Autodesk Fusion 360 part; units mm, degrees
(part 2 of 2)
equation "n_base_bolt = 4" comment "SKELETON P04 DECIDED: PM ruling 2026-10-31, J-BASE-01: bolts per panel along the band, evenly spaced"
equation "base_spigot_inset = spigot_inset" comment "SKELETON P04 DECIDED: J-BASE-01: the spigot rule (kept by this name for parts already linked)"
equation "base_side_y0 = pod_d / 2 - wall_depth + seam_gap" comment "SKELETON P04 CALCULATION: J-BASE-01: side bolt lines start at the side panel's front end (first bolt base_bolt_edge further on)"
equation "side_base_pitch = ( side_l - 2 * base_bolt_edge ) / ( n_base_bolt - 1 )" comment "SKELETON P04 CALCULATION: J-BASE-01 bolt pitch along a side panel"
equation "base_back_x0 = pod_w / 2 - outer_t - seam_gap" comment "SKELETON P04 CALCULATION: J-BASE-01: back bolt lines start at each back FRAME's outer end, X -/+ this (first bolt base_bolt_edge further in)"
equation "back_base_pitch = ( half_fw - 2 * base_bolt_edge ) / ( n_base_bolt - 1 )" comment "SKELETON P04 DECIDED: PM ruling 2026-10-31 (Reviewer 5 P2 on #58): J-BASE-01 pitch along a back panel, measured on the FRAME (half_fw), where the bolts go; 'panel end' means the frame end"
equation "ceil_bolt_z = pod_h - outer_t + frame_t / 2" comment "SKELETON P04 DECIDED: PM ruling 2026-10-31, J-CEIL-01 wall to ceiling: the bolt line on the ceiling frame's centre (Z 2374)"
equation "n_ceil_side_bolt = 4" comment "SKELETON P04 DECIDED: PM ruling 2026-10-31, J-CEIL-01: bolts along each side wall top"
equation "n_ceil_back_bolt = 4" comment "SKELETON P04 DECIDED: PM ruling 2026-10-31, J-CEIL-01: bolts along each back panel top, like the base (pitch about 253, every edge 350 or less; joints register: 82 bolts in all)"
equation "ceil_side_y0 = pod_d / 2 - wall_depth" comment "SKELETON P04 DECIDED: PM ruling 2026-10-31 (joints register): J-CEIL-01 side bolt lines start at Y -645, measured along the ceiling (first bolt bolt_edge_inset further on)"
equation "ceil_side_pitch = ( wall_depth - 2 * bolt_edge_inset ) / ( n_ceil_side_bolt - 1 )" comment "SKELETON P04 DECIDED: PM ruling 2026-10-31 (joints register): J-CEIL-01 pitch along a side wall top, over the ceiling's length (was over the side panel's)"
equation "ceil_back_x0 = pod_w / 2 - outer_t - seam_gap" comment "SKELETON P04 DECIDED: PM ruling 2026-10-31 (joints register): J-CEIL-01 back bolt lines start at each back frame's outer end, X -/+ this"
equation "ceil_back_pitch = ( half_fw - 2 * bolt_edge_inset ) / ( n_ceil_back_bolt - 1 )" comment "SKELETON P04 DECIDED: PM ruling 2026-10-31 (joints register): J-CEIL-01 pitch along a back panel top, on the frame (half_fw)"
equation "sk_ref = 5000 mm" comment "ASSUMPTION: sketch reference point offset: every sketch corner is dimensioned from a point at -sk_ref on both plane axes, so no dimension changes side when a corner crosses a pod centre line in an edit"
equation "fg_vis_zb = wall_z0" comment "CALCULATION: visible bottom of the fixed pane = the base band top (DL and DR stop there too, PM ruling 2026-10-31)"
equation "fg_vis_zt = dt_zb" comment "CALCULATION: visible top of the fixed pane = DT's underside"
equation "fg_gap = glass_gap" comment "CALCULATION: = the skeleton's glass_gap: the pane's free edge runs parallel to the door's latch edge, 4 mm off (PM ruling 2026-10-31; the skeleton's fix_xbl and fix_xtl follow the same rule since its update #58)"
equation "gu_prof_w = 15 mm" comment "SOURCE: Bohle BO5201571 aluminium U-profile 15 x 15 x 1.5 (hardware selection C5)"
equation "gu_prof_d = 15 mm" comment "SOURCE: as gu_prof_w"
equation "gu_prof_t = 1.5 mm" comment "SOURCE: as gu_prof_w"
equation "gu_w = gu_prof_w - 2 * gu_prof_t" comment "CALCULATION: inner width of the U-profile = the U-seal's outer width"
equation "gu_base = 2 mm" comment "ASSUMPTION: U-seal base under the glass edge; HOLD for Bohle's BO5201735 section drawing"
equation "gu_in_d = gu_prof_d - gu_prof_t" comment "CALCULATION: inner depth of the U-profile"
equation "fg_bite = gu_in_d - gu_base" comment "CALCULATION: glass cover in the hidden channels, 11.5 (PM ruling 2026-10-31); HOLD for the glass supplier's minimum"
equation "fg_r_len = sqrt(( fix_xbr - fix_xk ) * ( fix_xbr - fix_xk ) + ( fix_zk - fix_zb ) * ( fix_zk - fix_zb ))" comment "CALCULATION: length of the skeleton's right edge (bottom-right corner to the knee)"
equation "fg_rnx = ( fix_zk - fix_zb ) / fg_r_len" comment "CALCULATION: right edge outward normal, X"
equation "fg_rnz = ( fix_xk - fix_xbr ) / fg_r_len" comment "CALCULATION: right edge outward normal, Z"
equation "fg_rc = fg_rnx * ( pod_w / 2 - fix_xbr ) + fg_rnz * fix_zb" comment "CALCULATION: right edge line constant"
equation "fg_d_len = sqrt(( pod_w - fix_xtr - fix_xk ) * ( pod_w - fix_xtr - fix_xk ) + ( dt_zb - fix_zk ) * ( dt_zb - fix_zk ))" comment "CALCULATION: length of DR's diagonal inner edge (knee to DT's underside at X -pod_w/2 + fix_xtr)"
equation "fg_dnx = ( dt_zb - fix_zk ) / fg_d_len" comment "CALCULATION: diagonal outward normal, X"
equation "fg_dnz = ( pod_w - fix_xtr - fix_xk ) / fg_d_len" comment "CALCULATION: diagonal outward normal, Z"
equation "fg_dc = fg_dnx * ( pod_w / 2 - fix_xk ) + fg_dnz * fix_zk" comment "CALCULATION: diagonal line constant"
equation "fg_det = fg_rnx * fg_dnz - fg_rnz * fg_dnx" comment "CALCULATION: for the knee corner"
equation "fg_l_len = sqrt(( door_xbr - door_xtr ) * ( door_xbr - door_xtr ) + ( door_zt - door_zb ) * ( door_zt - door_zb ))" comment "CALCULATION: length of the door's latch edge"
equation "fg_lnx = ( door_zt - door_zb ) / fg_l_len" comment "CALCULATION: door latch edge normal toward the pane, X"
equation "fg_lnz = ( door_xbr - door_xtr ) / fg_l_len" comment "CALCULATION: door latch edge normal toward the pane, Z"
equation "fg_lc = fg_lnx * ( -pod_w / 2 + door_xbr ) + fg_lnz * door_zb" comment "CALCULATION: door latch edge line constant"
equation "dt_skin_t = 3 mm" comment "SOURCE: ACP 3 mm, EV3038 Dark Yellow (D-12; hardware selection A1)"
equation "dt_fo = dt_skin_t + bond_t" comment "CALCULATION: a frame tube's face from the skin's outer face: the 3 mm ACP and the 3 mm bond line (skeleton bond_t; the bond spec's joint, at least 12 wide x 3 thick, D-137), so every tube that bonds to the skin stands 3 mm off it (PM ruling 2026-11-01)"
equation "dt_back_t = 2 mm" comment "CONFIRMED: back plate 2 mm aluminium: J-FRONT-03 puts the ceiling bolts' rivnuts in it, 1.0 to 2.7 thick at each bolt (HOLD-10: 2 mm; PM ruling 2026-11-01)"
equation "dt_stop_gap = 2.26 mm" comment "SOURCE: J-FRONT-03: DT's back plate stands 2.26 in front of the ceiling's front face (Y -645), the stopped seam's gap (rivnut head 0.76 on a 1.5 stop washer, R-J5)"
equation "jf3_x0 = -1201.74 mm" comment "SOURCE: joints register 2.9: DT's bolt line starts at C1's frame end, X -1201.74"
equation "jf3_e = 220 mm" comment "SOURCE: R-J13: the end bolts 220 in from each end of the edge"
equation "jf3_z = 2374 mm" comment "SOURCE: R-J15: the bolt line on the ceiling's front tube centre, Z 2374"
equation "jf3_hole = 9.53 mm" comment "SOURCE: rivnut 838003 hole 9.53 +0.10/0 (joints register H-03)"
equation "jf3_tail = 14 mm" comment "CALCULATION: holes in the top back tube's back wall round the rivnut tails and the bolt tips, as J-FRONT-01's"
equation "fr_wtop = 40 mm" comment "CONFIRMED: the back ring's top tube 40 x 20, so the J-FRONT-03 rivnut tails at Z 2374 go into it (PM ruling 2026-11-01)"
equation "sp_x1 = -pod_w / 2 + dt_xr - 179 mm" comment "CONFIRMED: the round spigot hole, X 270: 36 in from the left end of DR's ledge tube (X 234 to 449)"
equation "sp_dx = 140 mm" comment "CONFIRMED: the slot 140 from the round hole (PM ruling 2026-11-01)"
equation "sp_y = -pod_d / 2 + decor_d - 12.88 mm" comment "CALCULATION: the spigots' Y, -657.88: the middle of where DR's ledge tube (Y -666.5 to -646.5) and DT's bottom back tube overlap"
equation "sp_hole = 8.5 mm" comment "SOURCE: R-J13: spigot hole 8.5 round at one end, 8.5 x 14 slot at the other"
equation "sp_slot = 14 mm" comment "SOURCE: R-J13: the slot 14 long along the edge"
equation "sp_skin = 16 mm" comment "CALCULATION: the underside's notch over DR's ledge reaches this far past each spigot, clear of the rivnut heads (12.96)"
equation "stop_fl = 20 mm" comment "SOURCE: the top stop's flange under DT's underside (the 20 x 20 x 2 angle), screwed up into the rail F02"
equation "stop_hole = 4.3 mm" comment "SOURCE: ISO 273 fine clearance for M4 countersunk screws through the flange, 2.1 diameters from its free edge (screw and rivnut: joints register numbers HOLD)"
equation "dt_m = ( dl_zo - dt_zb ) / dl_w" comment "CALCULATION: rise of the slope DT shares with DL, per unit of X"
equation "dt_k = sqrt(1 + dt_m * dt_m)" comment "CALCULATION: for pushing the slope line in by the skin"
equation "slot_clear = 1 mm" comment "ASSUMPTION: fitting clearance each side of the glass channel in the skin slot"
equation "door_top_cut = 2 mm" comment "DECIDED: PM ruling 2026-10-31: 6 mm gap from the leaf to DT for the catch"
equation "leaf_zt = door_zt - door_top_cut" comment "CALCULATION: top of the door leaf"
equation "st_l = 62 mm" comment "SOURCE: Sugatsune HT-MSG62 strike plate, 62 long (datasheet D2, Dec 2020)"
equation "st_a = 14.1 mm" comment "SOURCE: strike HT-MSG62-U10, A = 14.1"
equation "st_end = 25 mm" comment "ASSUMPTION: as the door unit: the strike's end in from the leaf's top latch corner"
equation "ca_l = 62 mm" comment "SOURCE: Sugatsune HT-MSG62 catch, 62 long (datasheet)"
equation "ca_d = 20 mm" comment "SOURCE: catch body depth 20 (datasheet)"
equation "ca_h = 26 mm" comment "SOURCE: catch body with its bracket, 26 below the frame (datasheet)"
equation "stop_gap = 4 mm" comment "SOURCE: athmer PS 1515 P Flex works in a 2 to 6 mm frame gap (selection C3): 4 nominal"
equation "ps_s = 15 mm" comment "SOURCE: athmer PS 1515 P Flex, 15 x 15 (selection C3)"
equation "stop_t = 2 mm" comment "ASSUMPTION: top stop: an aluminium angle leg 2 thick"
equation "stop_h = 20 mm" comment "SOURCE: top stop: a standard 20 x 20 x 2 aluminium angle (EN 755-9); its leg hangs 20 below DT's underside, past the seal"
equation "stop_end = 10 mm" comment "ASSUMPTION: the seal and stop stop 10 short of the catch"
equation "fr_w = 20 mm" comment "CALCULATION: frame tube 20 x 20 x 1.5, 6063-T6 (D-79): bending stiffness about v1's 16 x 16 x 1 steel box, as DR"
equation "fr_t = 1.5 mm" comment "CALCULATION: frame tube wall, as fr_w"
equation "rail_clear = -pod_d / 2 + decor_d - dt_stop_gap - dt_back_t - 2 * fr_w - ( -glass_y + gu_prof_w / 2 )" comment "CALCULATION: the catch and stop rail sits against the back ring's bottom tube, so it stands 2.24 behind the fixed glass's top channel (its back face at Y -691.5); J-FRONT-03 moved the back ring 1.26 forward"
equation "dt_fdx = fix_xtr - dt_x2" comment "CALCULATION: lower front facet in plan, along X"
equation "dt_fdy = pod_d / 2 - dt_y2" comment "CALCULATION: lower front facet in plan, along Y"
equation "dt_fl = sqrt(dt_fdx * dt_fdx + dt_fdy * dt_fdy)" comment "CALCULATION: lower front facet length in plan"
equation "dt_fnx = dt_fdy / dt_fl" comment "CALCULATION: lower front facet normal into DT, X"
equation "dt_fny = dt_fdx / dt_fl" comment "CALCULATION: lower front facet normal into DT, Y"
equation "dt_fc = dt_fnx * ( -pod_w / 2 + fix_xtr ) + dt_fny * ( -pod_d / 2 )" comment "CALCULATION: lower front facet constant"
equation "dt_cl = sqrt(( pod_d / 2 - ch_yb ) * ( pod_d / 2 - ch_yb ) + ( pod_h - ch_zlo ) * ( pod_h - ch_zlo ))" comment "CALCULATION: length of the top chamfer in the side view"
equation "dt_cny = -( pod_h - ch_zlo ) / dt_cl" comment "CALCULATION: top chamfer outward normal, Y"
equation "dt_cnz = ( pod_d / 2 - ch_yb ) / dt_cl" comment "CALCULATION: top chamfer outward normal, Z"
equation "dt_cc = dt_cny * ( -pod_d / 2 ) + dt_cnz * ch_zlo" comment "CALCULATION: top chamfer line constant"
equation "dt_jl = sqrt(( dt_xr - fix_xtr ) * ( dt_xr - fix_xtr ) + ( pod_d / 2 - ch_yb ) * ( pod_d / 2 - ch_yb ))" comment "CALCULATION: length of the DT-DR joint line in plan (v1's line to X 449)"
equation "dt_jnx = -( pod_d / 2 - ch_yb ) / dt_jl" comment "CALCULATION: DT-DR joint normal into DT, X"
equation "dt_jny = ( dt_xr - fix_xtr ) / dt_jl" comment "CALCULATION: DT-DR joint normal into DT, Y"
equation "dt_jc = dt_jnx * ( -pod_w / 2 + fix_xtr ) + dt_jny * ( -pod_d / 2 )" comment "CALCULATION: DT-DR joint constant"
equation "d2514 = sk_ref"
equation "d2515 = sk_ref"
equation "d2516 = ( -pod_w / 2 ) + sk_ref"
equation "d2517 = ( -pod_w / 2 + dl_x2 + 4 mm ) + sk_ref"
equation "d2518 = ( -pod_w / 2 + dt_x2 ) + sk_ref"
equation "d2519 = ( -pod_w / 2 + fix_xtr ) + sk_ref"
equation "d2520 = ( -pod_w / 2 + dt_xr ) + sk_ref"
equation "d2521 = ( -dl_y1 ) + sk_ref"
equation "d2522 = ( -dt_y3 ) + sk_ref"
equation "d2523 = ( -dt_y2 ) + sk_ref"
equation "d2524 = ( -pod_d / 2 ) + sk_ref"
equation "d2525 = ( -ch_yb ) + sk_ref"
equation "d2526 = ( ( -pod_d / 2 + decor_d - dt_stop_gap ) ) + sk_ref"
equation "d2527 = ( dt_zb ) * ( 1 )"
equation "d2528 = ( pod_h ) - ( dt_zb )"
equation "d2530 = sk_ref"
equation "d2531 = sk_ref"
equation "d2532 = ( -pod_w / 2 + dl_w ) + sk_ref"
equation "d2533 = ( -pod_w / 2 ) + sk_ref"
equation "d2534 = ( dt_zb ) + sk_ref"
equation "d2535 = ( dl_zo ) + sk_ref"
equation "d2536 = ( -pod_d / 2 ) * ( 1 )"
equation "d2537 = ( -pod_d / 2 + decor_d ) - ( -pod_d / 2 )"
equation "d2539 = sk_ref"
equation "d2540 = sk_ref"
equation "d2541 = ( ch_zlo ) + sk_ref"
equation "d2542 = ( pod_h ) + sk_ref"
equation "d2543 = ( -ch_yb ) + sk_ref"
equation "d2544 = ( -pod_d / 2 ) + sk_ref"
equation "d2545 = ( -pod_w / 2 ) * ( 1 )"
equation "d2546 = ( pod_w / 2 ) - ( -pod_w / 2 )"
equation "d2548 = dt_skin_t"
equation "d2549 = sk_ref"
equation "d2550 = sk_ref"
equation "d2551 = ( ( ( fg_dc + gu_prof_d - fg_dnz * ( fg_vis_zt ) ) / fg_dnx ) ) + sk_ref"
equation "d2552 = ( ( ( fg_lc + fg_gap - fg_lnz * ( fg_vis_zt + dt_skin_t + 1 mm ) ) / fg_lnx ) ) + sk_ref"
equation "d2553 = ( -glass_y - gu_prof_w / 2 - slot_clear ) + sk_ref"
equation "d2554 = ( -glass_y + gu_prof_w / 2 + slot_clear ) + sk_ref"
equation "d2555 = ( fg_vis_zt - 1 mm ) * ( 1 )"
equation "d2556 = ( fg_vis_zt + dt_skin_t + 1 mm ) - ( fg_vis_zt - 1 mm )"
equation "d2558 = sk_ref"
equation "d2559 = sk_ref"
equation "d2560 = ( ( sp_x1 + sp_dx + ( sp_slot - sp_hole ) / 2 + sp_skin ) ) + sk_ref"
equation "d2561 = ( ( sp_x1 - sp_skin ) ) + sk_ref"
equation "d2562 = ( sp_y - sp_skin ) + sk_ref"
equation "d2563 = ( ( -pod_d / 2 + decor_d - dt_stop_gap ) + 1 mm ) + sk_ref"
equation "d2564 = ( fg_vis_zt - 1 mm ) * ( 1 )"
equation "d2565 = ( fg_vis_zt + dt_skin_t + 1 mm ) - ( fg_vis_zt - 1 mm )"
equation "d2567 = sk_ref"
equation "d2568 = sk_ref"
equation "d2569 = ( ( -pod_w / 2 + dl_w + dt_skin_t * ( dt_k - 1 ) / dt_m ) ) + sk_ref"
equation "d2570 = ( -pod_w / 2 + dt_xr ) + sk_ref"
equation "d2571 = ( ( -pod_w / 2 + dl_w - ( pod_h - dt_skin_t - dt_zb - dt_skin_t * dt_k ) / dt_m ) ) + sk_ref"
equation "d2572 = ( dt_zb + dt_skin_t ) + sk_ref"
equation "d2573 = ( pod_h - dt_skin_t ) + sk_ref"
equation "d2574 = ( ( -pod_d / 2 + decor_d - dt_stop_gap ) - dt_back_t ) * ( 1 )"
equation "d2575 = ( ( -pod_d / 2 + decor_d - dt_stop_gap ) ) - ( ( -pod_d / 2 + decor_d - dt_stop_gap ) - dt_back_t )"
equation "d2577 = sk_ref"
equation "d2578 = sk_ref"
equation "d2579 = ( ( jf3_x0 + jf3_e + 0 * ( -pod_w / 2 + dt_xr - jf3_x0 - 2 * jf3_e ) / 3 ) ) + sk_ref"
equation "d2580 = ( jf3_z ) + sk_ref"
equation "d2581 = jf3_hole"
equation "d2582 = ( ( jf3_x0 + jf3_e + 1 * ( -pod_w / 2 + dt_xr - jf3_x0 - 2 * jf3_e ) / 3 ) ) + sk_ref"
equation "d2583 = ( jf3_z ) + sk_ref"
equation "d2584 = jf3_hole"
equation "d2585 = ( ( jf3_x0 + jf3_e + 2 * ( -pod_w / 2 + dt_xr - jf3_x0 - 2 * jf3_e ) / 3 ) ) + sk_ref"
equation "d2586 = ( jf3_z ) + sk_ref"
equation "d2587 = jf3_hole"
equation "d2588 = ( ( jf3_x0 + jf3_e + 3 * ( -pod_w / 2 + dt_xr - jf3_x0 - 2 * jf3_e ) / 3 ) ) + sk_ref"
equation "d2589 = ( jf3_z ) + sk_ref"
equation "d2590 = jf3_hole"
equation "d2591 = ( ( -pod_d / 2 + decor_d - dt_stop_gap ) - dt_back_t - 1 mm ) * ( 1 )"
equation "d2592 = ( ( -pod_d / 2 + decor_d - dt_stop_gap ) + 1 mm ) - ( ( -pod_d / 2 + decor_d - dt_stop_gap ) - dt_back_t - 1 mm )"
equation "d2594 = sk_ref"
equation "d2595 = sk_ref"
equation "d2596 = ( ( ( -pod_w / 2 + door_xbr - ( door_xbr - door_xtr ) * ( ( leaf_zt ) - door_zb ) / ( door_zt - door_zb ) ) - st_end ) - st_l / 2 + ca_l / 2 ) + sk_ref"
equation "d2597 = ( ( ( -pod_w / 2 + door_xbr - ( door_xbr - door_xtr ) * ( ( leaf_zt ) - door_zb ) / ( door_zt - door_zb ) ) - st_end ) - st_l / 2 - ca_l / 2 ) + sk_ref"
equation "d2598 = ( -glass_y + st_a / 2 ) + sk_ref"
equation "d2599 = ( -glass_y + st_a / 2 + ca_d ) + sk_ref"
equation "d2600 = ( fg_vis_zt - ca_h ) * ( 1 )"
equation "d2601 = ( fg_vis_zt ) - ( fg_vis_zt - ca_h )"
equation "d2603 = sk_ref"
equation "d2604 = sk_ref"
equation "d2605 = ( ( ( ( -pod_w / 2 + door_xbr - ( door_xbr - door_xtr ) * ( ( leaf_zt ) - door_zb ) / ( door_zt - door_zb ) ) - st_end ) - st_l / 2 - ca_l / 2 - stop_end ) ) + sk_ref"
equation "d2606 = ( ( -pod_w / 2 + door_xl ) ) + sk_ref"
equation "d2607 = ( -glass_y + glass_t / 2 ) + sk_ref"
equation "d2608 = ( -glass_y + glass_t / 2 + stop_gap ) + sk_ref"
equation "d2609 = ( fg_vis_zt - ps_s ) * ( 1 )"
equation "d2610 = ( fg_vis_zt ) - ( fg_vis_zt - ps_s )"
equation "d2612 = sk_ref"
equation "d2613 = sk_ref"
equation "d2614 = ( fg_vis_zt - stop_h ) + sk_ref"
equation "d2615 = ( fg_vis_zt - stop_t ) + sk_ref"
equation "d2616 = ( fg_vis_zt ) + sk_ref"
equation "d2617 = ( ( -glass_y + glass_t / 2 + stop_gap ) + stop_t ) + sk_ref"
equation "d2618 = ( ( -glass_y + glass_t / 2 + stop_gap ) + stop_fl ) + sk_ref"
equation "d2619 = ( ( -glass_y + glass_t / 2 + stop_gap ) ) + sk_ref"
equation "d2620 = ( ( -pod_w / 2 + door_xl ) ) * ( 1 )"
equation "d2621 = ( ( ( ( -pod_w / 2 + door_xbr - ( door_xbr - door_xtr ) * ( ( leaf_zt ) - door_zb ) / ( door_zt - door_zb ) ) - st_end ) - st_l / 2 - ca_l / 2 - stop_end ) ) - ( ( -pod_w / 2 + door_xl ) )"
equation "d2623 = sk_ref"
equation "d2624 = sk_ref"
equation "d2625 = ( ( ( -pod_w / 2 + door_xl ) + 50 mm + 0 * ( ( ( ( -pod_w / 2 + door_xbr - ( door_xbr - door_xtr ) * ( ( leaf_zt ) - door_zb ) / ( door_zt - door_zb ) ) - st_end ) - st_l / 2 - ca_l / 2 - stop_end ) - ( -pod_w / 2 + door_xl ) - 100 mm ) / 4 ) ) + sk_ref"
equation "d2626 = ( ( ( -glass_y + glass_t / 2 + stop_gap ) + stop_t + ( stop_fl - stop_t ) / 2 ) ) + sk_ref"
equation "d2627 = stop_hole"
equation "d2628 = ( ( ( -pod_w / 2 + door_xl ) + 50 mm + 1 * ( ( ( ( -pod_w / 2 + door_xbr - ( door_xbr - door_xtr ) * ( ( leaf_zt ) - door_zb ) / ( door_zt - door_zb ) ) - st_end ) - st_l / 2 - ca_l / 2 - stop_end ) - ( -pod_w / 2 + door_xl ) - 100 mm ) / 4 ) ) + sk_ref"
equation "d2629 = ( ( ( -glass_y + glass_t / 2 + stop_gap ) + stop_t + ( stop_fl - stop_t ) / 2 ) ) + sk_ref"
equation "d2630 = stop_hole"
equation "d2631 = ( ( ( -pod_w / 2 + door_xl ) + 50 mm + 2 * ( ( ( ( -pod_w / 2 + door_xbr - ( door_xbr - door_xtr ) * ( ( leaf_zt ) - door_zb ) / ( door_zt - door_zb ) ) - st_end ) - st_l / 2 - ca_l / 2 - stop_end ) - ( -pod_w / 2 + door_xl ) - 100 mm ) / 4 ) ) + sk_ref"
equation "d2632 = ( ( ( -glass_y + glass_t / 2 + stop_gap ) + stop_t + ( stop_fl - stop_t ) / 2 ) ) + sk_ref"
equation "d2633 = stop_hole"
equation "d2634 = ( ( ( -pod_w / 2 + door_xl ) + 50 mm + 3 * ( ( ( ( -pod_w / 2 + door_xbr - ( door_xbr - door_xtr ) * ( ( leaf_zt ) - door_zb ) / ( door_zt - door_zb ) ) - st_end ) - st_l / 2 - ca_l / 2 - stop_end ) - ( -pod_w / 2 + door_xl ) - 100 mm ) / 4 ) ) + sk_ref"
equation "d2635 = ( ( ( -glass_y + glass_t / 2 + stop_gap ) + stop_t + ( stop_fl - stop_t ) / 2 ) ) + sk_ref"
equation "d2636 = stop_hole"
equation "d2637 = ( ( ( -pod_w / 2 + door_xl ) + 50 mm + 4 * ( ( ( ( -pod_w / 2 + door_xbr - ( door_xbr - door_xtr ) * ( ( leaf_zt ) - door_zb ) / ( door_zt - door_zb ) ) - st_end ) - st_l / 2 - ca_l / 2 - stop_end ) - ( -pod_w / 2 + door_xl ) - 100 mm ) / 4 ) ) + sk_ref"
equation "d2638 = ( ( ( -glass_y + glass_t / 2 + stop_gap ) + stop_t + ( stop_fl - stop_t ) / 2 ) ) + sk_ref"
equation "d2639 = stop_hole"
equation "d2640 = ( fg_vis_zt - stop_t - 1 mm ) * ( 1 )"
equation "d2641 = ( fg_vis_zt + 1 mm ) - ( fg_vis_zt - stop_t - 1 mm )"
equation "d2643 = sk_ref"
equation "d2644 = sk_ref"
equation "d2645 = ( ( ( ( ( dt_zb + dt_m * ( -pod_w / 2 + dl_w ) ) / dt_k + dt_skin_t ) - ( ( ( fg_vis_zt + dt_fo ) ) * ( 1 / dt_k ) ) ) / ( dt_m / dt_k ) ) ) + sk_ref"
equation "d2646 = ( ( -( -( -pod_w / 2 + dt_xr ) ) ) ) + sk_ref"
equation "d2647 = ( ( -( ( -( -pod_w / 2 + dt_xr ) + 0 mm + fr_w ) ) ) ) + sk_ref"
equation "d2648 = ( ( ( ( ( dt_zb + dt_m * ( -pod_w / 2 + dl_w ) ) / dt_k + dt_skin_t + fr_w ) - ( ( ( fg_vis_zt + dt_fo + fr_w ) ) * ( 1 / dt_k ) ) ) / ( dt_m / dt_k ) ) ) + sk_ref"
equation "d2649 = ( ( ( ( dt_m / dt_k ) * ( ( fg_vis_zt + dt_fo ) ) ) / ( dt_m / dt_k ) ) ) + sk_ref"
equation "d2650 = ( ( -( -( ( fg_vis_zt + dt_fo + fr_w ) ) ) ) ) + sk_ref"
equation "d2651 = ( ( ( -pod_d / 2 + decor_d - dt_stop_gap ) - dt_back_t - fr_w ) ) * ( 1 )"
equation "d2652 = ( ( ( -pod_d / 2 + decor_d - dt_stop_gap ) - dt_back_t ) ) - ( ( ( -pod_d / 2 + decor_d - dt_stop_gap ) - dt_back_t - fr_w ) )"
equation "d2654 = fr_t"
equation "d2655 = sk_ref"
equation "d2656 = sk_ref"
equation "d2657 = ( ( -( -( -pod_w / 2 + dt_xr ) ) ) ) + sk_ref"
equation "d2658 = ( ( -( ( -( -pod_w / 2 + dt_xr ) + 0 mm + fr_w ) ) ) ) + sk_ref"
equation "d2659 = ( ( -( -( ( fg_vis_zt + dt_fo ) ) ) ) ) + sk_ref"
equation "d2660 = ( ( -( ( -pod_h + dt_fo ) ) ) ) + sk_ref"
equation "d2661 = ( ( -( ( -pod_h + dt_fo + fr_wtop ) ) ) ) + sk_ref"
equation "d2662 = ( ( -( -( ( fg_vis_zt + dt_fo + fr_w ) ) ) ) ) + sk_ref"
equation "d2663 = ( ( ( -pod_d / 2 + decor_d - dt_stop_gap ) - dt_back_t - fr_w ) ) * ( 1 )"
equation "d2664 = ( ( ( -pod_d / 2 + decor_d - dt_stop_gap ) - dt_back_t ) ) - ( ( ( -pod_d / 2 + decor_d - dt_stop_gap ) - dt_back_t - fr_w ) )"
equation "d2666 = fr_t"
equation "d2667 = sk_ref"
equation "d2668 = sk_ref"
equation "d2669 = ( ( -( -( -pod_w / 2 + dt_xr ) ) ) ) + sk_ref"
equation "d2670 = ( ( ( ( ( -pod_h + dt_fo ) ) * ( 1 / dt_k ) - ( -( ( ( dt_zb + dt_m * ( -pod_w / 2 + dl_w ) ) / dt_k + dt_skin_t ) ) ) ) / ( -( -( dt_m / dt_k ) ) ) ) ) + sk_ref"
equation "d2671 = ( ( ( ( ( -pod_h + dt_fo + fr_wtop ) ) * ( 1 / dt_k ) - ( -( ( ( dt_zb + dt_m * ( -pod_w / 2 + dl_w ) ) / dt_k + dt_skin_t + fr_w ) ) ) ) / ( -( -( dt_m / dt_k ) ) ) ) ) + sk_ref"
equation "d2672 = ( ( -( ( -( -pod_w / 2 + dt_xr ) + 0 mm + fr_w ) ) ) ) + sk_ref"
equation "d2673 = ( ( -( ( -pod_h + dt_fo ) ) ) ) + sk_ref"
equation "d2674 = ( ( ( -( ( dt_m / dt_k ) * ( ( -pod_h + dt_fo + fr_wtop ) ) ) ) / ( -( -( dt_m / dt_k ) ) ) ) ) + sk_ref"
equation "d2675 = ( ( ( -pod_d / 2 + decor_d - dt_stop_gap ) - dt_back_t - fr_w ) ) * ( 1 )"
equation "d2676 = ( ( ( -pod_d / 2 + decor_d - dt_stop_gap ) - dt_back_t ) ) - ( ( ( -pod_d / 2 + decor_d - dt_stop_gap ) - dt_back_t - fr_w ) )"
equation "d2678 = fr_t"
equation "d2679 = sk_ref"
equation "d2680 = sk_ref"
equation "d2681 = ( ( ( ( ( -pod_h + dt_fo ) ) * ( 1 / dt_k ) - ( -( ( ( dt_zb + dt_m * ( -pod_w / 2 + dl_w ) ) / dt_k + dt_skin_t ) ) ) ) / ( -( -( dt_m / dt_k ) ) ) ) ) + sk_ref"
equation "d2682 = ( ( ( ( ( dt_zb + dt_m * ( -pod_w / 2 + dl_w ) ) / dt_k + dt_skin_t ) - ( ( ( fg_vis_zt + dt_fo ) ) * ( 1 / dt_k ) ) ) / ( dt_m / dt_k ) ) ) + sk_ref"
equation "d2683 = ( ( ( ( ( dt_zb + dt_m * ( -pod_w / 2 + dl_w ) ) / dt_k + dt_skin_t + fr_w ) - ( ( ( fg_vis_zt + dt_fo + fr_w ) ) * ( 1 / dt_k ) ) ) / ( dt_m / dt_k ) ) ) + sk_ref"
equation "d2684 = ( ( ( ( ( -pod_h + dt_fo + fr_wtop ) ) * ( 1 / dt_k ) - ( -( ( ( dt_zb + dt_m * ( -pod_w / 2 + dl_w ) ) / dt_k + dt_skin_t + fr_w ) ) ) ) / ( -( -( dt_m / dt_k ) ) ) ) ) + sk_ref"
equation "d2685 = ( ( ( -( ( dt_m / dt_k ) * ( ( -pod_h + dt_fo ) ) ) ) / ( -( -( dt_m / dt_k ) ) ) ) ) + sk_ref"
equation "d2686 = ( ( ( ( dt_m / dt_k ) * ( ( fg_vis_zt + dt_fo ) ) ) / ( dt_m / dt_k ) ) ) + sk_ref"
equation "d2687 = ( ( ( ( dt_m / dt_k ) * ( ( fg_vis_zt + dt_fo + fr_w ) ) ) / ( dt_m / dt_k ) ) ) + sk_ref"
equation "d2688 = ( ( ( -( ( dt_m / dt_k ) * ( ( -pod_h + dt_fo + fr_wtop ) ) ) ) / ( -( -( dt_m / dt_k ) ) ) ) ) + sk_ref"
equation "d2689 = ( ( ( -pod_d / 2 + decor_d - dt_stop_gap ) - dt_back_t - fr_w ) ) * ( 1 )"
equation "d2690 = ( ( ( -pod_d / 2 + decor_d - dt_stop_gap ) - dt_back_t ) ) - ( ( ( -pod_d / 2 + decor_d - dt_stop_gap ) - dt_back_t - fr_w ) )"
equation "d2692 = fr_t"
equation "d2693 = sk_ref"
equation "d2694 = sk_ref"
equation "d2695 = ( ( ( -pod_w / 2 + dl_w + -pod_w / 2 + dt_xr ) / 2 - fr_w / 2 ) + fr_w ) + sk_ref"
equation "d2696 = ( ( ( -pod_w / 2 + dl_w + -pod_w / 2 + dt_xr ) / 2 - fr_w / 2 ) ) + sk_ref"
equation "d2697 = ( ( fg_vis_zt + dt_fo ) + fr_w ) + sk_ref"
equation "d2698 = ( pod_h - dt_fo - fr_wtop ) + sk_ref"
equation "d2699 = ( ( ( -pod_d / 2 + decor_d - dt_stop_gap ) - dt_back_t - fr_w ) ) * ( 1 )"
equation "d2700 = ( ( ( -pod_d / 2 + decor_d - dt_stop_gap ) - dt_back_t ) ) - ( ( ( -pod_d / 2 + decor_d - dt_stop_gap ) - dt_back_t - fr_w ) )"
equation "d2702 = fr_t"
equation "d2703 = sk_ref"
equation "d2704 = sk_ref"
equation "d2705 = ( ( ( ( ( dt_fc + dt_fo ) ) * dt_jny - ( dt_jc * dt_fny ) ) / ( dt_fnx * dt_jny - ( dt_jnx * dt_fny ) ) ) ) + sk_ref"
equation "d2706 = ( ( ( ( ( dt_fc + dt_fo + fr_w ) ) * dt_jny - ( dt_jc * dt_fny ) ) / ( dt_fnx * dt_jny - ( dt_jnx * dt_fny ) ) ) ) + sk_ref"
equation "d2707 = ( ( ( -( ( ( -pod_w / 2 + dt_x2 ) ) * dt_fny ) ) / ( -dt_fny ) ) ) + sk_ref"
equation "d2708 = ( ( ( dt_fnx * ( ( -pod_w / 2 + dt_x2 ) ) - ( ( dt_fc + dt_fo ) ) ) / ( -dt_fny ) ) ) + sk_ref"
equation "d2709 = ( ( ( dt_fnx * dt_jc - ( dt_jnx * ( ( dt_fc + dt_fo ) ) ) ) / ( dt_fnx * dt_jny - ( dt_jnx * dt_fny ) ) ) ) + sk_ref"
equation "d2710 = ( ( ( dt_fnx * dt_jc - ( dt_jnx * ( ( dt_fc + dt_fo + fr_w ) ) ) ) / ( dt_fnx * dt_jny - ( dt_jnx * dt_fny ) ) ) ) + sk_ref"
equation "d2711 = ( ( ( dt_fnx * ( ( -pod_w / 2 + dt_x2 ) ) - ( ( dt_fc + dt_fo + fr_w ) ) ) / ( -dt_fny ) ) ) + sk_ref"
equation "d2712 = ( ( fg_vis_zt + dt_fo ) ) * ( 1 )"
equation "d2713 = ( ( fg_vis_zt + dt_fo ) + fr_w ) - ( ( fg_vis_zt + dt_fo ) )"
equation "d2715 = fr_t"
equation "d2716 = sk_ref"
equation "d2717 = sk_ref"
equation "d2718 = ( ( ( dt_jc - ( ( ( -glass_y + gu_prof_w / 2 + rail_clear ) ) * dt_jny ) ) / dt_jnx ) ) + sk_ref"
equation "d2719 = ( ( ( -( ( ( -pod_w / 2 + dt_xr ) ) * dt_jny ) ) / ( -dt_jny ) ) ) + sk_ref"
equation "d2720 = ( ( -pod_w / 2 + dl_w - ( dt_fo - dt_skin_t * dt_k ) / dt_m ) ) + sk_ref"
equation "d2721 = ( ( -glass_y + gu_prof_w / 2 + rail_clear ) ) + sk_ref"
equation "d2722 = ( ( ( dt_jnx * ( ( -pod_w / 2 + dt_xr ) ) - dt_jc ) / ( -dt_jny ) ) ) + sk_ref"
equation "d2723 = ( ( ( -glass_y + gu_prof_w / 2 + rail_clear ) + fr_w ) ) + sk_ref"
equation "d2724 = ( ( fg_vis_zt + dt_fo ) ) * ( 1 )"
equation "d2725 = ( ( fg_vis_zt + dt_fo ) + fr_w ) - ( ( fg_vis_zt + dt_fo ) )"
equation "d2727 = fr_t"
equation "d2728 = sk_ref"
equation "d2729 = sk_ref"
equation "d2730 = ( ( ( ( -dt_cny ) * ( dt_cnz * ( ( -( ( ( -dt_y2 + dt_fo / dt_fny ) ) * ( -dt_cnz ) ) ) / ( -( -dt_cnz ) ) ) - dt_cny * ( ( ( -dt_cny ) * ( ( -dt_y2 + dt_fo / dt_fny ) ) - ( ( -dt_cc + dt_fo ) ) ) / ( -( -dt_cnz ) ) ) ) - ( dt_cnz * ( ( -dt_cc + dt_fo ) ) ) ) / ( ( -dt_cny ) * ( -dt_cny ) - ( dt_cnz * ( -dt_cnz ) ) ) ) ) + sk_ref"
equation "d2731 = ( ( ( ( -dt_cny ) * ( ( dt_cnz * ( ( -( ( ( -dt_y2 + dt_fo / dt_fny ) ) * ( -dt_cnz ) ) ) / ( -( -dt_cnz ) ) ) - dt_cny * ( ( ( -dt_cny ) * ( ( -dt_y2 + dt_fo / dt_fny ) ) - ( ( -dt_cc + dt_fo ) ) ) / ( -( -dt_cnz ) ) ) + fr_w ) ) - ( dt_cnz * ( ( -dt_cc + dt_fo ) ) ) ) / ( ( -dt_cny ) * ( -dt_cny ) - ( dt_cnz * ( -dt_cnz ) ) ) ) ) + sk_ref"
equation "d2732 = ( ( ( ( -dt_cny ) * ( ( dt_cnz * ( ( -( ( ( -dt_y2 + dt_fo / dt_fny ) ) * ( -dt_cnz ) ) ) / ( -( -dt_cnz ) ) ) - dt_cny * ( ( ( -dt_cny ) * ( ( -dt_y2 + dt_fo / dt_fny ) ) - ( ( -dt_cc + dt_fo ) ) ) / ( -( -dt_cnz ) ) ) + fr_w ) ) - ( dt_cnz * ( ( -dt_cc + dt_fo + fr_w ) ) ) ) / ( ( -dt_cny ) * ( -dt_cny ) - ( dt_cnz * ( -dt_cnz ) ) ) ) ) + sk_ref"
equation "d2733 = ( ( ( ( -dt_cny ) * ( dt_cnz * ( ( -( ( ( -dt_y2 + dt_fo / dt_fny ) ) * ( -dt_cnz ) ) ) / ( -( -dt_cnz ) ) ) - dt_cny * ( ( ( -dt_cny ) * ( ( -dt_y2 + dt_fo / dt_fny ) ) - ( ( -dt_cc + dt_fo ) ) ) / ( -( -dt_cnz ) ) ) ) - ( dt_cnz * ( ( -dt_cc + dt_fo + fr_w ) ) ) ) / ( ( -dt_cny ) * ( -dt_cny ) - ( dt_cnz * ( -dt_cnz ) ) ) ) ) + sk_ref"
equation "d2734 = ( ( ( ( ( -dt_cc + dt_fo ) ) * ( -dt_cny ) - ( ( dt_cnz * ( ( -( ( ( -dt_y2 + dt_fo / dt_fny ) ) * ( -dt_cnz ) ) ) / ( -( -dt_cnz ) ) ) - dt_cny * ( ( ( -dt_cny ) * ( ( -dt_y2 + dt_fo / dt_fny ) ) - ( ( -dt_cc + dt_fo ) ) ) / ( -( -dt_cnz ) ) ) ) * ( -dt_cnz ) ) ) / ( ( -dt_cny ) * ( -dt_cny ) - ( dt_cnz * ( -dt_cnz ) ) ) ) ) + sk_ref"
equation "d2735 = ( ( ( ( ( -dt_cc + dt_fo ) ) * ( -dt_cny ) - ( ( ( dt_cnz * ( ( -( ( ( -dt_y2 + dt_fo / dt_fny ) ) * ( -dt_cnz ) ) ) / ( -( -dt_cnz ) ) ) - dt_cny * ( ( ( -dt_cny ) * ( ( -dt_y2 + dt_fo / dt_fny ) ) - ( ( -dt_cc + dt_fo ) ) ) / ( -( -dt_cnz ) ) ) + fr_w ) ) * ( -dt_cnz ) ) ) / ( ( -dt_cny ) * ( -dt_cny ) - ( dt_cnz * ( -dt_cnz ) ) ) ) ) + sk_ref"
equation "d2736 = ( ( ( ( ( -dt_cc + dt_fo + fr_w ) ) * ( -dt_cny ) - ( ( ( dt_cnz * ( ( -( ( ( -dt_y2 + dt_fo / dt_fny ) ) * ( -dt_cnz ) ) ) / ( -( -dt_cnz ) ) ) - dt_cny * ( ( ( -dt_cny ) * ( ( -dt_y2 + dt_fo / dt_fny ) ) - ( ( -dt_cc + dt_fo ) ) ) / ( -( -dt_cnz ) ) ) + fr_w ) ) * ( -dt_cnz ) ) ) / ( ( -dt_cny ) * ( -dt_cny ) - ( dt_cnz * ( -dt_cnz ) ) ) ) ) + sk_ref"
equation "d2737 = ( ( ( ( ( -dt_cc + dt_fo + fr_w ) ) * ( -dt_cny ) - ( ( dt_cnz * ( ( -( ( ( -dt_y2 + dt_fo / dt_fny ) ) * ( -dt_cnz ) ) ) / ( -( -dt_cnz ) ) ) - dt_cny * ( ( ( -dt_cny ) * ( ( -dt_y2 + dt_fo / dt_fny ) ) - ( ( -dt_cc + dt_fo ) ) ) / ( -( -dt_cnz ) ) ) ) * ( -dt_cnz ) ) ) / ( ( -dt_cny ) * ( -dt_cny ) - ( dt_cnz * ( -dt_cnz ) ) ) ) ) + sk_ref"
equation "d2738 = ( ( -pod_w / 2 + dt_x2 ) ) * ( 1 )"
equation "d2739 = ( ( ( dt_jc - dt_jny * ( -dt_y2 + dt_fo / dt_fny ) ) / dt_jnx ) ) - ( ( -pod_w / 2 + dt_x2 ) )"
equation "d2741 = fr_t"
equation "d2742 = sk_ref"
equation "d2743 = sk_ref"
equation "d2744 = ( ( ( -( ( ( ( -pod_w / 2 + dt_x2 + 280 mm ) + fr_w ) ) * dt_fny ) ) / ( -dt_fny ) ) ) + sk_ref"
equation "d2745 = ( ( -pod_w / 2 + dt_x2 + 280 mm ) ) + sk_ref"
equation "d2746 = ( ( ( dt_fnx * ( ( -pod_w / 2 + dt_x2 + 280 mm ) ) - ( ( dt_fc + dt_fo + fr_w ) ) ) / ( -dt_fny ) ) ) + sk_ref"
equation "d2747 = ( ( ( dt_fnx * ( ( ( -pod_w / 2 + dt_x2 + 280 mm ) + fr_w ) ) - ( ( dt_fc + dt_fo + fr_w ) ) ) / ( -dt_fny ) ) ) + sk_ref"
equation "d2748 = ( ( -glass_y + gu_prof_w / 2 + rail_clear ) ) + sk_ref"
equation "d2749 = ( ( fg_vis_zt + dt_fo ) ) * ( 1 )"
equation "d2750 = ( ( fg_vis_zt + dt_fo ) + fr_w ) - ( ( fg_vis_zt + dt_fo ) )"
equation "d2752 = fr_t"
equation "d2753 = sk_ref"
equation "d2754 = sk_ref"
equation "d2755 = ( ( ( -( ( ( ( ( ( -pod_w / 2 + door_xbr - ( door_xbr - door_xtr ) * ( ( leaf_zt ) - door_zb ) / ( door_zt - door_zb ) ) - st_end - st_l / 2 ) - fr_w / 2 ) + fr_w ) ) * dt_fny ) ) / ( -dt_fny ) ) ) + sk_ref"
equation "d2756 = ( ( ( ( -pod_w / 2 + door_xbr - ( door_xbr - door_xtr ) * ( ( leaf_zt ) - door_zb ) / ( door_zt - door_zb ) ) - st_end - st_l / 2 ) - fr_w / 2 ) ) + sk_ref"
equation "d2757 = ( ( ( dt_fnx * ( ( ( ( -pod_w / 2 + door_xbr - ( door_xbr - door_xtr ) * ( ( leaf_zt ) - door_zb ) / ( door_zt - door_zb ) ) - st_end - st_l / 2 ) - fr_w / 2 ) ) - ( ( dt_fc + dt_fo + fr_w ) ) ) / ( -dt_fny ) ) ) + sk_ref"
equation "d2758 = ( ( ( dt_fnx * ( ( ( ( ( -pod_w / 2 + door_xbr - ( door_xbr - door_xtr ) * ( ( leaf_zt ) - door_zb ) / ( door_zt - door_zb ) ) - st_end - st_l / 2 ) - fr_w / 2 ) + fr_w ) ) - ( ( dt_fc + dt_fo + fr_w ) ) ) / ( -dt_fny ) ) ) + sk_ref"
equation "d2759 = ( ( -glass_y + gu_prof_w / 2 + rail_clear ) ) + sk_ref"
equation "d2760 = ( ( fg_vis_zt + dt_fo ) ) * ( 1 )"
equation "d2761 = ( ( fg_vis_zt + dt_fo ) + fr_w ) - ( ( fg_vis_zt + dt_fo ) )"
equation "d2763 = fr_t"
equation "d2764 = sk_ref"
equation "d2765 = sk_ref"
equation "d2766 = ( ( ( ( -dt_cny ) * ( ( dt_cnz * ( ( -( ( ( -dt_y2 + dt_fo / dt_fny ) ) * ( -dt_cnz ) ) ) / ( -( -dt_cnz ) ) ) - dt_cny * ( ( ( -dt_cny ) * ( ( -dt_y2 + dt_fo / dt_fny ) ) - ( ( -dt_cc + dt_fo ) ) ) / ( -( -dt_cnz ) ) ) + fr_w ) ) - ( dt_cnz * ( ( -dt_cc + dt_fo ) ) ) ) / ( ( -dt_cny ) * ( -dt_cny ) - ( dt_cnz * ( -dt_cnz ) ) ) ) ) + sk_ref"
equation "d2767 = ( ( ( ( -dt_cny ) * ( pod_h - dt_fo ) ) / ( -dt_cny ) ) ) + sk_ref"
equation "d2768 = ( ( ( ( -dt_cny ) * ( ( ( -pod_d / 2 + decor_d - dt_stop_gap ) - dt_back_t - fr_w ) ) - ( ( -dt_cc + dt_fo + fr_w ) ) ) / ( -( -dt_cnz ) ) ) ) + sk_ref"
equation "d2769 = ( ( ( ( -dt_cny ) * ( ( dt_cnz * ( ( -( ( ( -dt_y2 + dt_fo / dt_fny ) ) * ( -dt_cnz ) ) ) / ( -( -dt_cnz ) ) ) - dt_cny * ( ( ( -dt_cny ) * ( ( -dt_y2 + dt_fo / dt_fny ) ) - ( ( -dt_cc + dt_fo ) ) ) / ( -( -dt_cnz ) ) ) + fr_w ) ) - ( dt_cnz * ( ( -dt_cc + dt_fo + fr_w ) ) ) ) / ( ( -dt_cny ) * ( -dt_cny ) - ( dt_cnz * ( -dt_cnz ) ) ) ) ) + sk_ref"
equation "d2770 = ( ( ( ( ( -dt_cc + dt_fo ) ) * ( -dt_cny ) - ( ( ( dt_cnz * ( ( -( ( ( -dt_y2 + dt_fo / dt_fny ) ) * ( -dt_cnz ) ) ) / ( -( -dt_cnz ) ) ) - dt_cny * ( ( ( -dt_cny ) * ( ( -dt_y2 + dt_fo / dt_fny ) ) - ( ( -dt_cc + dt_fo ) ) ) / ( -( -dt_cnz ) ) ) + fr_w ) ) * ( -dt_cnz ) ) ) / ( ( -dt_cny ) * ( -dt_cny ) - ( dt_cnz * ( -dt_cnz ) ) ) ) ) + sk_ref"
equation "d2771 = ( ( ( ( -dt_cc + dt_fo ) - ( ( pod_h - dt_fo ) * ( -dt_cnz ) ) ) / ( -dt_cny ) ) ) + sk_ref"
equation "d2772 = ( ( ( -( ( ( ( -pod_d / 2 + decor_d - dt_stop_gap ) - dt_back_t - fr_w ) ) * ( -dt_cnz ) ) ) / ( -( -dt_cnz ) ) ) ) + sk_ref"
equation "d2773 = ( ( ( ( ( -dt_cc + dt_fo + fr_w ) ) * ( -dt_cny ) - ( ( ( dt_cnz * ( ( -( ( ( -dt_y2 + dt_fo / dt_fny ) ) * ( -dt_cnz ) ) ) / ( -( -dt_cnz ) ) ) - dt_cny * ( ( ( -dt_cny ) * ( ( -dt_y2 + dt_fo / dt_fny ) ) - ( ( -dt_cc + dt_fo ) ) ) / ( -( -dt_cnz ) ) ) + fr_w ) ) * ( -dt_cnz ) ) ) / ( ( -dt_cny ) * ( -dt_cny ) - ( dt_cnz * ( -dt_cnz ) ) ) ) ) + sk_ref"
equation "d2774 = ( ( -pod_w / 2 + dt_x2 + 280 mm ) ) * ( 1 )"
equation "d2775 = ( ( -pod_w / 2 + dt_x2 + 280 mm ) + fr_w ) - ( ( -pod_w / 2 + dt_x2 + 280 mm ) )"
equation "d2777 = fr_t"
equation "d2778 = ( ( ( ( -pod_w / 2 + door_xbr - ( door_xbr - door_xtr ) * ( ( leaf_zt ) - door_zb ) / ( door_zt - door_zb ) ) - st_end - st_l / 2 ) - fr_w / 2 ) ) - ( ( -pod_w / 2 + dt_x2 + 280 mm ) )"
equation "d2784 = ( ( ( ( dt_jc - dt_jny * ( -dt_y2 + dt_fo / dt_fny ) ) / dt_jnx ) - 2 * fr_w ) ) - ( ( -pod_w / 2 + dt_x2 + 280 mm ) )"
equation "d2790 = sk_ref"
equation "d2791 = sk_ref"
equation "d2792 = ( ( jf3_x0 + jf3_e + 0 * ( -pod_w / 2 + dt_xr - jf3_x0 - 2 * jf3_e ) / 3 ) ) + sk_ref"
equation "d2793 = ( jf3_z ) + sk_ref"
equation "d2794 = jf3_tail"
equation "d2795 = ( ( jf3_x0 + jf3_e + 1 * ( -pod_w / 2 + dt_xr - jf3_x0 - 2 * jf3_e ) / 3 ) ) + sk_ref"
equation "d2796 = ( jf3_z ) + sk_ref"
equation "d2797 = jf3_tail"
equation "d2798 = ( ( jf3_x0 + jf3_e + 2 * ( -pod_w / 2 + dt_xr - jf3_x0 - 2 * jf3_e ) / 3 ) ) + sk_ref"
equation "d2799 = ( jf3_z ) + sk_ref"
equation "d2800 = jf3_tail"
equation "d2801 = ( ( jf3_x0 + jf3_e + 3 * ( -pod_w / 2 + dt_xr - jf3_x0 - 2 * jf3_e ) / 3 ) ) + sk_ref"
equation "d2802 = ( jf3_z ) + sk_ref"
equation "d2803 = jf3_tail"
equation "d2804 = ( ( -pod_d / 2 + decor_d - dt_stop_gap ) - dt_back_t - fr_t - 1 mm ) * ( 1 )"
equation "d2805 = ( ( -pod_d / 2 + decor_d - dt_stop_gap ) - dt_back_t + 0.5 mm ) - ( ( -pod_d / 2 + decor_d - dt_stop_gap ) - dt_back_t - fr_t - 1 mm )"
equation "d2807 = sk_ref"
equation "d2808 = sk_ref"
equation "d2809 = ( sp_x1 ) + sk_ref"
equation "d2810 = ( sp_y ) + sk_ref"
equation "d2811 = sp_hole"
equation "d2812 = ( sp_x1 + sp_dx - ( sp_slot - sp_hole ) / 2 ) + sk_ref"
equation "d2813 = ( sp_y ) + sk_ref"
equation "d2814 = sp_hole"
equation "d2815 = ( sp_x1 + sp_dx + ( sp_slot - sp_hole ) / 2 ) + sk_ref"
equation "d2816 = ( sp_y ) + sk_ref"
equation "d2817 = sp_hole"
equation "d2818 = ( fg_vis_zt + dt_fo - 1 mm ) * ( 1 )"
equation "d2819 = ( fg_vis_zt + dt_fo + fr_t + 0.5 mm ) - ( fg_vis_zt + dt_fo - 1 mm )"
equation "d2821 = sk_ref"
equation "d2822 = sk_ref"
equation "d2823 = ( sp_x1 + sp_dx + ( sp_slot - sp_hole ) / 2 ) + sk_ref"
equation "d2824 = ( sp_x1 + sp_dx - ( sp_slot - sp_hole ) / 2 ) + sk_ref"
equation "d2825 = ( sp_y - sp_hole / 2 ) + sk_ref"
equation "d2826 = ( sp_y + sp_hole / 2 ) + sk_ref"
equation "d2827 = ( fg_vis_zt + dt_fo - 1 mm ) * ( 1 )"
equation "d2828 = ( fg_vis_zt + dt_fo + fr_t + 0.5 mm ) - ( fg_vis_zt + dt_fo - 1 mm )"
named bodies: "DT SKIN ACP 3", "DT BACK PLATE AL 2", "CATCH HT-MSG62 ENVELOPE", "FRAME-STOP SEAL PS 1515 - TOP (COMPRESSED TO THE GAP)", "DOOR TOP STOP ANGLE 20 X 20 X 2", "B01 BACK RING BOTTOM 20 x 20 x 1.5", "B02 BACK RING DR JOINT 20 x 20 x 1.5", "B03 BACK RING TOP 40 x 20 x 1.5", "B04 BACK RING SLOPE OVER DL 20 x 20 x 1.5", "B05 BACK RING POST 20 x 20 x 1.5", "F01 FRONT FACET TUBE 20 x 20 x 1.5", "F02 CATCH AND STOP RAIL 20 x 20 x 1.5", "F03 CHAMFER TUBE ALONG X 20 x 20 x 1.5", "R01 UNDERSIDE CROSS TUBE LEFT 20 x 20 x 1.5", "R02 UNDERSIDE CROSS TUBE OVER THE CATCH 20 x 20 x 1.5", "C01 CHAMFER CROSS TUBE LEFT 20 x 20 x 1.5"
